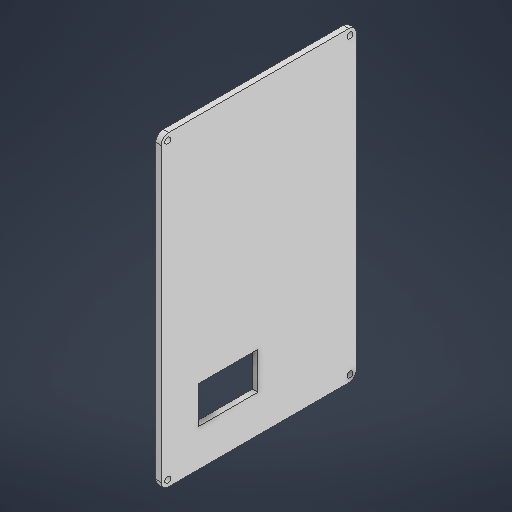
# Autodesk Inventor part: tapa4
Saved by Autodesk Inventor 2027 (Build 310192000, 192)
## iProperties
Created: 2026-11-02
Part Number: tapa4
Material: Generic
Document SubType Name: Modeling
Designer: USUARIO
Density: 1 g/cm^3
Appearance: Default
Author: USUARIO
Autodesk Inventor part; units mm, degrees
ref_plane "YZ Plane" through (0, 0, 0) normal (1, 0, 0) x (0, 1, 0)
ref_plane "XZ Plane" through (0, 0, 0) normal (0, 1, 0) x (-1, 0, 0)
ref_plane "XY Plane" through (0, 0, 0) normal (0, 0, 1) x (1, 0, 0)
sketch "Sketch1" plane through (0, 0, 0) normal (1, 0, 0) x (0, 1, 0)
  line L0 (82.5, 52.5) -> (-82.5, 52.5)
  line L1 (-82.5, 52.5) -> (-82.5, -52.5)
  line L2 (-82.5, -52.5) -> (82.5, -52.5)
  line L3 (82.5, -52.5) -> (82.5, 52.5)
  line L4 (82.5, 52.5) -> (-82.5, -52.5) construction
  line L5 (-82.5, 52.5) -> (82.5, -52.5) construction
  point P0 (0, 0)
  dimension "d0" = 165
  dimension "d1" = 105
  constraints: 12 end point, 2 midpoint, 2 parallel, 1 horizontal, 1 perpendicular
  measures "d0" distance between parallel lines of L1 L3
  measures "d1" distance between parallel lines of L2 L0
extrude "Extrusion1" add sketch "Sketch1" along normal blind 3
sketch "Sketch2" plane through (3, 0, 0) normal (1, 0, 0) x (0, 0, -1)
  circle A0 centre (49, 79) radius 1.6
  line L0 (52.5, -82.5) -> (52.5, 82.5) projected
  line L1 (52.5, 82.5) -> (-52.5, 82.5) projected
  circle A1 centre (49, -79) radius 1.6
  circle A2 centre (-49, 79) radius 1.6
  circle A3 centre (-49, -79) radius 1.6
  line L2 (-52.5, -82.5) -> (52.5, -82.5) projected
  line L3 (-52.5, 82.5) -> (-52.5, -82.5) projected
  point P0 (0, 0)
  dimension "d4" = 3.2
  dimension "d5" = 3.5
  dimension "d6" = 3.5
  dimension "d7" = 3.2
  dimension "d8" = 3.2
  dimension "d9" = 3.2
  dimension "d10" = 3.5
  dimension "d11" = 3.5
  dimension "d12" = 3.5
  dimension "d13" = 3.5
  dimension "d14" = 3.5
  dimension "d15" = 3.5
  constraints: 4 centre point
  measures "d4" diameter of A0
  measures "d5" distance from line of L0 A0.centre
  measures "d6" distance from line of L1 A0.centre
  measures "d7" diameter of A1
  measures "d8" diameter of A2
  measures "d9" diameter of A3
  measures "d10" distance from line of L2 A1.centre
  measures "d11" distance from line of L0 A1.centre
  measures "d12" distance from line of L3 A3.centre
  measures "d13" distance from line of L2 A3.centre
  measures "d14" distance from line of L3 A2.centre
  measures "d15" distance from line of L1 A2.centre
extrude "Extrusion2" cut sketch "Sketch2" against normal blind 6 contours A0 | A1 | A2 | A3
fillet "Fillet1" radius 4 1 edges at (1.5, 82.5, -52.5)
fillet "Fillet2" radius 4 1 edges at (1.5, 82.5, 52.5)
fillet "Fillet3" radius 4 1 edges at (1.5, -82.5, 52.5)
fillet "Fillet4" radius 4 1 edges at (1.5, -82.5, -52.5)
sketch "Sketch3" plane through (3, 0, 0) normal (1, 0, 0) x (0, 0, -1)
  line L0 (-0.5, -42.5) -> (-32.5, -42.5)
  line L1 (-32.5, -42.5) -> (-32.5, -62.5)
  line L2 (-32.5, -62.5) -> (-0.5, -62.5)
  line L3 (-0.5, -62.5) -> (-0.5, -42.5)
  line L4 (-48.5, -82.5) -> (48.5, -82.5) projected
  line L5 (-52.5, 78.5) -> (-52.5, -78.5) projected
  point P0 (0, 0)
  point P1 (-16.5, -62.5)
  dimension "d22" = 32
  dimension "d23" = 20
  dimension "d24" = 20
  dimension "d25" = 20
  constraints: 8 end point, 2 parallel, 1 horizontal, 1 midpoint, 1 perpendicular
  measures "d22" distance of L2.end L1.end
  measures "d23" distance of L1.end L0.end
  measures "d24" distance from line of L4 point (-16.5, -62.5)
  measures "d25" distance between parallel lines of L1 L5
extrude "Extrusion3" cut sketch "Sketch3" against normal blind 3
body "Solid1"
